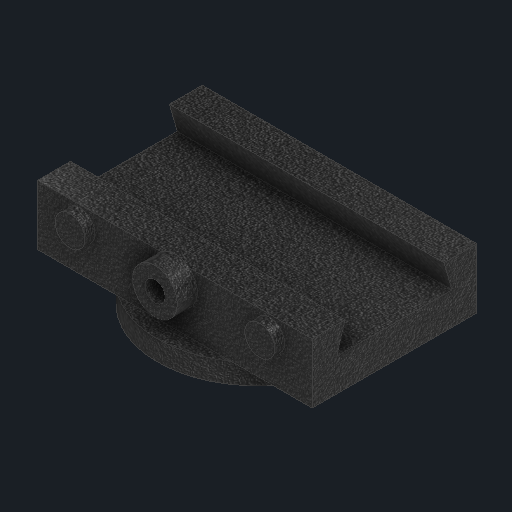
# Autodesk Inventor part: saddle_vixen
Saved by Autodesk Inventor 2027.1 (Build 311270010, 270A)
## iProperties
Created: 2026-11-04
Part Number: saddle_vixen
Material: Generic
Description: Vixen-style dovetail saddle
Document SubType Name: Modeling
Designer: Claude (from photos)
Density: 1 g/cm^3
Appearance: Black Cast
Mass: 164.652 g
Surface Area: 292.877 cm^2
Volume: 164.652 cm^3
Author: alexg
Autodesk Inventor part; units mm, degrees
ref_plane "Work Plane1" through (0, 105, 0) normal (0, 1, 0) x (-1, 0, 0)
sketch "Dec shaft flange sketch" plane through (0, 105, 0) normal (0, 1, 0) x (-1, 0, 0)
  circle A0 centre (-187, 0) radius 40
  constraints: 1 centre point
extrude "Dec shaft flange" add sketch "Dec shaft flange sketch" along normal blind 8
ref_plane "Work Plane2" through (0, 113, 0) normal (0, 1, 0) x (-1, 0, 0)
sketch "Saddle block sketch" plane through (0, 113, 0) normal (0, 1, 0) x (-1, 0, 0)
  line L0 (-132, -33) -> (-242, -33)
  line L1 (-242, -33) -> (-242, 33)
  line L2 (-242, 33) -> (-132, 33)
  line L3 (-132, 33) -> (-132, -33)
  constraints: 8 end point, 2 parallel, 1 horizontal, 1 perpendicular
extrude "Saddle block" add sketch "Saddle block sketch" along normal blind 24
ref_plane "Work Plane3" through (131, 0, 0) normal (1, 0, 0) x (0, 1, 0)
sketch "Vixen dovetail slot sketch" plane through (131, 0, 0) normal (1, 0, 0) x (0, 1, 0)
  line L0 (126, -23) -> (126, 23)
  line L1 (126, 23) -> (138, 19.5)
  line L2 (138, 19.5) -> (138, -19.5)
  line L3 (138, -19.5) -> (126, -23)
  constraints: 8 end point
extrude "Vixen dovetail slot" cut sketch "Vixen dovetail slot sketch" along normal blind 112
ref_plane "Work Plane4" through (0, 0, 33) normal (0, 0, 1) x (1, 0, 0)
sketch "Clamp boss sketch" plane through (0, 0, 33) normal (0, 0, 1) x (1, 0, 0)
  circle A0 centre (187, 130) radius 9
  constraints: 1 centre point
extrude "Clamp boss" add sketch "Clamp boss sketch" along normal blind 8
ref_plane "Work Plane5" through (0, 0, 33) normal (0, 0, 1) x (1, 0, 0)
sketch "Safety screw bosses sketch" plane through (0, 0, 33) normal (0, 0, 1) x (1, 0, 0)
  circle A0 centre (225, 130) radius 6
  circle A1 centre (149, 130) radius 6
  constraints: 2 centre point
extrude "Safety screw bosses" add sketch "Safety screw bosses sketch" along normal blind 4
ref_plane "Work Plane6" through (0, 0, 41) normal (0, 0, 1) x (1, 0, 0)
sketch "Clamp thread sketch" plane through (0, 0, 41) normal (0, 0, 1) x (1, 0, 0)
  circle A0 centre (187, 130) radius 4
  constraints: 1 centre point
extrude "Clamp thread" cut sketch "Clamp thread sketch" against normal blind 30
body "Solid1"
